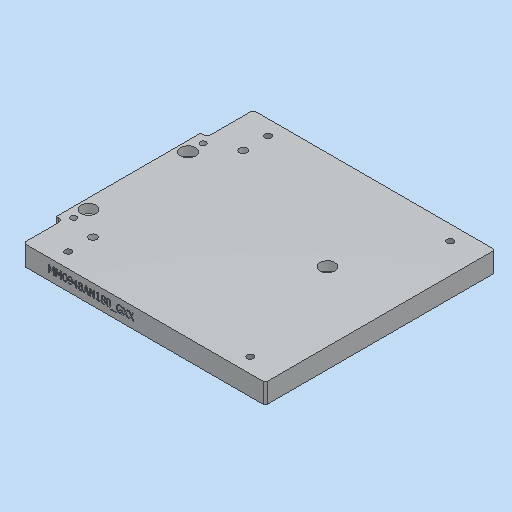
# Autodesk Inventor part: MM0948AN180_G01_106
Saved by Autodesk Inventor 2023.3 (Build 273359000, 359)
## iProperties
Part Number: MM0948AN180_G01_106
Material: 3.3547 AlMg4,5Mn0,7 - AW 5083
Description: =<RBPARTNOTITLE2>
Document SubType Name: Modeling
Designer: ric7an
Mass: 3048.24 g
Surface Area: 1379.15 cm^2
Volume: 1128.98 cm^3
Density: 2.7 g/cm^3
Appearance: Aluminium AnP
Created: 2023-03-23
RBDOCUMENTTYPE: DRF
RBDOCUMENTVERSION: 00
RBDRAWINGMAINSCALE: 1:1
RBDRAWINGMISSINGSPEC: --
RBDRAWINGVOLUME: --
RBGBEDGESIN1: +0,5
RBGBEDGESIN2: +0,2
RBGBEDGESOUT1: -0,3
RBGBEDGESOUT2: -0,1
RBMATERIAL: =<Material>
RBMATMEETS: --
RBMATNO: =<Part Number>
RBPARTMADEOF: 20 x 276 x 249,5 (FM)
RBPARTNO: SIEHE MNR
RBPARTNOTITLE1: manufactured part
RBPARTNOTITLE2: Anfertigungsteil
RBPARTSAFETYINDICATOR: --
RBSURFACE: anodised colourless
RBSURFACE2: eloxiert farblos
RBZEDGESNORM: ISO13715:2002-06
RBZGENDIMCLASS: m
RBZGENDIMNORM: ISO 2768-1:1989-11
RBZGENGEOCLASS: H
RBZGENGEONORM: ISO 2768-2:1989-11
RBZSURFACENORM: ISO13D2:2002-02
RBZTOLERANCENORM: ISO 14405-1:2010-12
AnP_Material: =<Material>
AnP_TemplVers: 20190222
AnP_Kategorie: 1
MaxAbmaße: 20 x 276 x 249,5 (FM)
AnP_Kommentar_aktuell: =<Comments>
AnP_Material_aktuell: =<Material>
Author: FH/Wi
Keywords: =<RBPARTMADEOF>
Comments: =<RBSURFACE2>
Revision Number: 01
Autodesk Inventor part; units mm, degrees
ref_plane "YZ Plane" through (0, 0, 0) normal (1, 0, 0) x (0, 1, 0)
ref_plane "XZ Plane" through (0, 0, 0) normal (0, 1, 0) x (-1, 0, 0)
ref_plane "XY Plane" through (0, 0, 0) normal (0, 0, 1) x (1, 0, 0)
sketch "Skizze1" plane through (0, 0, 0) normal (0, 0, 1) x (1, 0, 0)
  line L0 (-128, 115.5) -> (121.5, 115.5)
  line L1 (121.5, 115.5) -> (121.5, -115.5)
  line L2 (121.5, -115.5) -> (-128, -115.5)
  line L3 (-128, -115.5) -> (-128, 115.5)
  line L4 (0, 161.7) -> (0, -161.7) projected
  line L5 (-177.9, 0) -> (171.4, 0) projected
  point P0 (0, 0)
  dimension "d0" = 249.5
  dimension "d1" = 231
  dimension "d97" = 121.5
  constraints: 8 end point, 2 parallel, 1 horizontal, 1 perpendicular, 1 other
  measures "d0" distance of L0.start L0.end
  measures "d1" distance of L0.end L1.end
  measures "d97" distance between parallel lines of L1 L4
extrude "Extrusion1" add sketch "Skizze1" along normal blind 20
sketch "Skizze3" plane through (0, 0, 20) normal (0, 0, 1) x (1, 0, 0)
  line L0 (-128, 115.5) -> (-128, -115.5) projected
  line L1 (0, 193.2) -> (0, -193.2) projected
  line L2 (-177.9, 0) -> (171.4, 0) projected
  line L3 (121.5, 115.5) -> (-128, 115.5) projected
  point P0 (0, 0)
  point P1 (-118, 61.5)
  point P2 (-118, 46.5)
  point P3 (-118, -53.5)
  point P4 (-118, -68.5)
  point P5 (52, 16.5)
  dimension "d20" = 100
  dimension "d21" = 130
  dimension "d22" = 15
  dimension "d23" = 10
  dimension "d24" = 170
  dimension "d48" = 46.5
  dimension "d52" = 45
  constraints: 3 vertical alignment
  measures "d20" distance of point (-118, -53.5) point (-118, 46.5)
  measures "d21" distance of point (-118, -68.5) point (-118, 61.5)
  measures "d22" distance of point (-118, 46.5) point (-118, 61.5)
  measures "d23" distance from line of point (-118, 61.5) L0
  measures "d24" horizontal distance of point (52, 16.5) point (-118, -53.5)
  measures "d48" distance from line of L2 point (-118, 46.5)
  measures "d52" vertical distance of point (52, 16.5) point (-118, 61.5)
hole "Bohrung3" at (-118, 46.5, 20) at (-118, -53.5, 20) at (52, 16.5, 20) direction (0, 0, -1) diameter 9 end through all counterbore diameter 15 counterbore depth 9 clearance for "Inbusschraube ISO 4762  versenkt" size "M8" standard "ISO"
hole "Bohrung4" at (-118, 61.5, 20) at (-118, -68.5, 20) direction (0, 0, -1) diameter 6 end through all
sketch "Skizze10" plane through (0, 0, 20) normal (0, 0, 1) x (1, 0, 0)
  line L0 (-128, 115.5) -> (-121.5, 115.5)
  line L1 (-121.5, 115.5) -> (-121.5, 69)
  line L2 (-121.5, 69) -> (-128, 69)
  line L3 (-128, 69) -> (-128, 115.5)
  line L4 (121.5, -115.5) -> (121.5, 115.5) projected
  line L5 (-121.5, -76) -> (-128, -76)
  line L6 (-128, -76) -> (-128, -115.5)
  line L7 (-128, -115.5) -> (-121.5, -115.5)
  line L8 (-121.5, -115.5) -> (-121.5, -76)
  circle A0 centre (-118, 46.5) radius 7.5 projected
  circle A1 centre (-118, -53.5) radius 7.5 projected
  line L9 (-118, 46.5) -> (-118, -53.5)
  line L10 (-133.8016, -3.5) -> (-118, -3.5)
  point P0 (0, 0)
  dimension "d84" = 243
  dimension "d85" = 145
  constraints: 20 end point, 4 parallel, 3 horizontal, 2 coincident, 2 perpendicular, 1 collinear, 1 midpoint, 1 vertical, 1 other
  measures "d84" distance between parallel lines of L4 L1
  measures "d85" distance between parallel lines of L5 L2
extrude "Extrusion6" cut sketch "Skizze10" against normal through all contours L0 L1 L2 L3 | L8 L7 L6 L5
chamfer "Fase1" distance 2 angle 45 4 edges at (-121.5, -115.5, 10) (121.5, -115.5, 10) (121.5, 115.5, 10) (-121.5, 115.5, 10)
sketch "Skizze11" plane through (0, 0, 20) normal (0, 0, 1) x (1, 0, 0)
  line L0 (-91.5, 100.5) -> (91.5, 100.5)
  line L1 (91.5, 100.5) -> (91.5, -100.5)
  line L2 (91.5, -100.5) -> (-91.5, -100.5)
  line L3 (-91.5, -100.5) -> (-91.5, 100.5)
  line L4 (121.5, -115.5) -> (121.5, 115.5) projected
  line L5 (121.5, 115.5) -> (-121.5, 115.5) projected
  point P0 (0, 0)
  point P1 (91.5, 0)
  point P2 (121.5, 0)
  point P3 (0, 100.5)
  point P4 (0, 115.5)
  dimension "d95" = 183
  dimension "d96" = 201
  constraints: 8 end point, 4 midpoint, 2 coincident, 2 parallel, 1 horizontal, 1 horizontal alignment, 1 perpendicular, 1 vertical alignment
  measures "d95" distance of L0.start L0.end
  measures "d96" distance of L0.end L1.end
hole "Bohrung7" at (91.5, -100.5, 20) at (-91.5, -100.5, 20) at (-91.5, 100.5, 20) at (91.5, 100.5, 20) direction (0, 0, -1) diameter 6.647 end through all thread size "M8x1.25" designation "M8" class "6H" standard "ISO Metric profile"
fillet "Rundung3" radius 4 2 edges at (-121.5, -76, 10) (-121.5, 69, 10)
sketch "Skizze12" plane through (0, 0, 20) normal (0, 0, 1) x (1, 0, 0)
  circle A0 centre (-91.5, 100.5) radius 3.3235 projected
  circle A1 centre (-91.5, -100.5) radius 3.3235 projected
  line L0 (-91.5, 100.5) -> (-91.5, 75.5)
  line L1 (-91.5, -75.5) -> (-91.5, -100.5)
  point P0 (0, 0)
  dimension "d109" = 25
  dimension "d117" = 25
  constraints: 4 end point, 1 vertical
  measures "d109" distance of L0.start L0.end
  measures "d117" distance of L1.start L1.end
hole "Bohrung8" at (-91.5, -75.5, 20) at (-91.5, 75.5, 20) direction (0, 0, -1) diameter 8 depth 14 tip angle 118
sketch "Skizze13" plane through (0, 0, 20) normal (0, 0, 1) x (1, 0, 0)
  circle A0 centre (-91.5, -75.5) radius 4 projected
  circle A1 centre (-91.5, 75.5) radius 4 projected
  point P0 (0, 0)
  constraints: 2 coincident
hole "Bohrung9" at (-91.5, -75.5, 20) at (-91.5, 75.5, 20) direction (0, 0, -1) diameter 5.5 end through all
sketch "Skizze14" plane through (-119.5, -115.5, 0) normal (0, -1, 0) x (1, 0, 0)
  line L0 (22.2225, 14.2828) -> (108.8886, 14.2828) construction
  line L1 (108.8886, 14.2828) -> (108.8886, 5.7172) construction
  line L2 (108.8886, 5.7172) -> (22.2225, 5.7172) construction
  line L3 (22.2225, 5.7172) -> (22.2225, 14.2828) construction
  line L4 (-8.5, 0) -> (-8.5, 20) projected
  line L5 (28.9332, 7.124) -> (28.0029, 7.124)
  line L6 (28.0029, 7.124) -> (28.0029, 13.154)
  line L7 (28.0029, 13.154) -> (26.1763, 9.0527)
  line L8 (26.1763, 9.0527) -> (25.609, 9.0527)
  line L9 (25.609, 9.0527) -> (23.7995, 13.154)
  line L10 (23.7995, 13.154) -> (23.7995, 7.124)
  line L11 (23.7995, 7.124) -> (22.9316, 7.124)
  line L12 (22.9316, 7.124) -> (22.9316, 14.124)
  line L13 (22.9316, 14.124) -> (24.2022, 14.124)
  line L14 (24.2022, 14.124) -> (25.9494, 10.2269)
  line L15 (25.9494, 10.2269) -> (27.6398, 14.124)
  line L16 (27.6398, 14.124) -> (28.9332, 14.124)
  line L17 (28.9332, 14.124) -> (28.9332, 7.124)
  line L18 (36.3529, 7.124) -> (35.4226, 7.124)
  line L19 (35.4226, 7.124) -> (35.4226, 13.154)
  line L20 (35.4226, 13.154) -> (33.5961, 9.0527)
  line L21 (33.5961, 9.0527) -> (33.0288, 9.0527)
  line L22 (33.0288, 9.0527) -> (31.2192, 13.154)
  line L23 (31.2192, 13.154) -> (31.2192, 7.124)
  line L24 (31.2192, 7.124) -> (30.3513, 7.124)
  line L25 (30.3513, 7.124) -> (30.3513, 14.124)
  line L26 (30.3513, 14.124) -> (31.622, 14.124)
  line L27 (31.622, 14.124) -> (33.3692, 10.2269)
  line L28 (33.3692, 10.2269) -> (35.0596, 14.124)
  line L29 (35.0596, 14.124) -> (36.3529, 14.124)
  line L30 (36.3529, 14.124) -> (36.3529, 7.124)
  spline S0 degree 2 poles (41.9291, 10.624) (41.9291, 8.7407) (40.8343, 6.9765) (39.6941, 6.9765) knots 0 0 0 1 2 2 2
  spline S1 degree 2 poles (39.6941, 6.9765) (38.5369, 6.9765) (37.4534, 8.7747) (37.4534, 10.6183) knots 0 0 0 1 2 2 2
  spline S2 degree 2 poles (37.4534, 10.6183) (37.4534, 12.513) (38.5482, 14.2658) (39.6941, 14.2658) knots 0 0 0 1 2 2 2
  spline S3 degree 2 poles (39.6941, 14.2658) (40.8457, 14.2658) (41.9291, 12.4506) (41.9291, 10.624) knots 0 0 0 1 2 2 2
  spline S4 degree 2 poles (40.7265, 8.4911) (40.8627, 8.8371) (40.9761, 9.9036) (40.9761, 10.624) knots 0 0 0 1 2 2 2
  spline S5 degree 2 poles (40.9761, 10.624) (40.9761, 11.3444) (40.8627, 12.4052) (40.7209, 12.7626) knots 0 0 0 1 2 2 2
  spline S6 degree 2 poles (40.7209, 12.7626) (40.579, 13.1199) (40.0855, 13.4887) (39.6941, 13.4887) knots 0 0 0 1 2 2 2
  spline S7 degree 2 poles (39.6941, 13.4887) (39.3027, 13.4887) (38.7978, 13.1199) (38.6504, 12.7512) knots 0 0 0 1 2 2 2
  spline S8 degree 2 poles (38.6504, 12.7512) (38.5085, 12.3938) (38.4064, 11.3047) (38.4064, 10.6183) knots 0 0 0 1 2 2 2
  spline S9 degree 2 poles (38.4064, 10.6183) (38.4064, 9.8809) (38.4972, 8.8938) (38.6447, 8.5081) knots 0 0 0 1 2 2 2
  spline S10 degree 2 poles (38.6447, 8.5081) (38.7808, 8.1451) (39.2857, 7.7536) (39.6941, 7.7536) knots 0 0 0 1 2 2 2
  spline S11 degree 2 poles (39.6941, 7.7536) (40.0799, 7.7536) (40.5847, 8.1224) (40.7265, 8.4911) knots 0 0 0 1 2 2 2
  spline S12 degree 2 poles (42.6325, 11.8493) (42.6325, 12.3882) (42.9842, 13.2844) (43.2905, 13.6078) knots 0 0 0 1 2 2 2
  spline S13 degree 2 poles (43.2905, 13.6078) (43.5799, 13.9198) (44.4251, 14.2658) (44.8562, 14.2658) knots 0 0 0 1 2 2 2
  spline S14 degree 2 poles (44.8562, 14.2658) (45.3384, 14.2658) (46.1212, 13.9425) (46.4105, 13.6361) knots 0 0 0 1 2 2 2
  spline S15 degree 2 poles (46.4105, 13.6361) (46.7735, 13.2504) (47.1706, 12.0024) (47.1706, 11.0438) knots 0 0 0 1 2 2 2
  spline S16 degree 2 poles (47.1706, 11.0438) (47.1706, 10.1759) (46.7792, 8.6216) (46.3991, 8.1053) knots 0 0 0 1 2 2 2
  spline S17 degree 2 poles (46.3991, 8.1053) (45.9964, 7.5608) (44.8619, 6.9878) (44.0337, 6.9878) knots 0 0 0 1 2 2 2
  spline S18 degree 2 poles (44.0337, 6.9878) (43.8465, 6.9878) (43.421, 7.0276) (43.2395, 7.0843) knots 0 0 0 1 2 2 2
  line L31 (43.2395, 7.0843) -> (43.2395, 7.9862)
  line L32 (43.2395, 7.9862) -> (43.2849, 7.9862)
  spline S19 degree 2 poles (43.2849, 7.9862) (43.404, 7.9182) (43.9032, 7.799) (44.1585, 7.799) knots 0 0 0 1 2 2 2
  spline S20 degree 2 poles (44.1585, 7.799) (45.0774, 7.799) (46.1269, 9.013) (46.2006, 10.1361) knots 0 0 0 1 2 2 2
  spline S21 degree 2 poles (46.2006, 10.1361) (45.8262, 9.8809) (45.1455, 9.6483) (44.7427, 9.6483) knots 0 0 0 1 2 2 2
  spline S22 degree 2 poles (44.7427, 9.6483) (44.357, 9.6483) (43.716, 9.8185) (43.3927, 10.0624) knots 0 0 0 1 2 2 2
  spline S23 degree 2 poles (43.3927, 10.0624) (43.0183, 10.3517) (42.6325, 11.231) (42.6325, 11.8493) knots 0 0 0 1 2 2 2
  spline S24 degree 2 poles (46.2233, 11.2536) (46.2233, 11.9627) (45.9623, 12.859) (45.7298, 13.1029) knots 0 0 0 1 2 2 2
  spline S25 degree 2 poles (45.7298, 13.1029) (45.5256, 13.3298) (45.1001, 13.5) (44.8505, 13.5) knots 0 0 0 1 2 2 2
  spline S26 degree 2 poles (44.8505, 13.5) (44.2719, 13.5) (43.5855, 12.6718) (43.5855, 11.889) knots 0 0 0 1 2 2 2
  spline S27 degree 2 poles (43.5855, 11.889) (43.5855, 11.4465) (43.8124, 10.8736) (44.062, 10.6694) knots 0 0 0 1 2 2 2
  spline S28 degree 2 poles (44.062, 10.6694) (44.2435, 10.5219) (44.6917, 10.4254) (44.9526, 10.4254) knots 0 0 0 1 2 2 2
  spline S29 degree 2 poles (44.9526, 10.4254) (45.2533, 10.4254) (45.9453, 10.6353) (46.2063, 10.8112) knots 0 0 0 1 2 2 2
  spline S30 degree 2 poles (46.2063, 10.8112) (46.2119, 10.8793) (46.2233, 11.1118) (46.2233, 11.2536) knots 0 0 0 1 2 2 2
  line L33 (52.5823, 9.5292) -> (51.7484, 9.5292)
  line L34 (51.7484, 9.5292) -> (51.7484, 7.124)
  line L35 (51.7484, 7.124) -> (50.8465, 7.124)
  line L36 (50.8465, 7.124) -> (50.8465, 9.5292)
  line L37 (50.8465, 9.5292) -> (47.7549, 9.5292)
  line L38 (47.7549, 9.5292) -> (47.7549, 10.5162)
  line L39 (47.7549, 10.5162) -> (50.8862, 14.124)
  line L40 (50.8862, 14.124) -> (51.7484, 14.124)
  line L41 (51.7484, 14.124) -> (51.7484, 10.2836)
  line L42 (51.7484, 10.2836) -> (52.5823, 10.2836)
  line L43 (52.5823, 10.2836) -> (52.5823, 9.5292)
  line L44 (50.8465, 10.2836) -> (50.8465, 13.0178)
  line L45 (50.8465, 13.0178) -> (48.4923, 10.2836)
  line L46 (48.4923, 10.2836) -> (50.8465, 10.2836)
  spline S31 degree 2 poles (55.4469, 6.9652) (54.9251, 6.9652) (54.0685, 7.2771) (53.7679, 7.5665) knots 0 0 0 1 2 2 2
  spline S32 degree 2 poles (53.7679, 7.5665) (53.4729, 7.8501) (53.1666, 8.6216) (53.1666, 9.0583) knots 0 0 0 1 2 2 2
  spline S33 degree 2 poles (53.1666, 9.0583) (53.1666, 9.6256) (53.7735, 10.5786) (54.3521, 10.8622) knots 0 0 0 1 2 2 2
  line L47 (54.3521, 10.8622) -> (54.3521, 10.8906)
  spline S34 degree 2 poles (54.3521, 10.8906) (53.8359, 11.1912) (53.3367, 11.906) (53.3367, 12.4392) knots 0 0 0 1 2 2 2
  spline S35 degree 2 poles (53.3367, 12.4392) (53.3367, 13.2277) (54.528, 14.2828) (55.4469, 14.2828) knots 0 0 0 1 2 2 2
  spline S36 degree 2 poles (55.4469, 14.2828) (56.3999, 14.2828) (57.5515, 13.2844) (57.5515, 12.5016) knots 0 0 0 1 2 2 2
  spline S37 degree 2 poles (57.5515, 12.5016) (57.5515, 12.0308) (57.0012, 11.1118) (56.485, 10.8509) knots 0 0 0 1 2 2 2
  line L48 (56.485, 10.8509) -> (56.485, 10.8225)
  spline S38 degree 2 poles (56.485, 10.8225) (57.0977, 10.5389) (57.7273, 9.722) (57.7273, 9.0754) knots 0 0 0 1 2 2 2
  spline S39 degree 2 poles (57.7273, 9.0754) (57.7273, 8.1791) (56.4226, 6.9652) (55.4469, 6.9652) knots 0 0 0 1 2 2 2
  spline S40 degree 2 poles (56.763, 8.9846) (56.763, 9.4157) (56.4226, 9.9263) (55.9405, 10.1872) knots 0 0 0 1 2 2 2
  spline S41 degree 2 poles (55.9405, 10.1872) (55.7816, 10.278) (55.2484, 10.4878) (54.9137, 10.624) knots 0 0 0 1 2 2 2
  spline S42 degree 2 poles (54.9137, 10.624) (54.528, 10.3687) (54.1139, 9.6086) (54.1139, 9.1264) knots 0 0 0 1 2 2 2
  spline S43 degree 2 poles (54.1139, 9.1264) (54.1139, 8.4911) (54.8797, 7.6629) (55.4583, 7.6629) knots 0 0 0 1 2 2 2
  spline S44 degree 2 poles (55.4583, 7.6629) (56.0482, 7.6629) (56.763, 8.372) (56.763, 8.9846) knots 0 0 0 1 2 2 2
  spline S45 degree 2 poles (56.6325, 12.4903) (56.6325, 12.9611) (56.0029, 13.5908) (55.4413, 13.5908) knots 0 0 0 1 2 2 2
  spline S46 degree 2 poles (55.4413, 13.5908) (54.9307, 13.5908) (54.2784, 13.0292) (54.2784, 12.547) knots 0 0 0 1 2 2 2
  spline S47 degree 2 poles (54.2784, 12.547) (54.2784, 12.201) (54.6131, 11.7188) (54.9478, 11.5259) knots 0 0 0 1 2 2 2
  spline S48 degree 2 poles (54.9478, 11.5259) (55.0896, 11.4465) (55.6909, 11.1686) (55.9348, 11.0891) knots 0 0 0 1 2 2 2
  spline S49 degree 2 poles (55.9348, 11.0891) (56.3432, 11.4011) (56.6325, 12.0648) (56.6325, 12.4903) knots 0 0 0 1 2 2 2
  line L49 (58.028, 7.124) -> (60.3878, 14.124)
  line L50 (60.3878, 14.124) -> (61.5337, 14.124)
  line L51 (61.5337, 14.124) -> (63.8935, 7.124)
  line L52 (63.8935, 7.124) -> (62.9121, 7.124)
  line L53 (62.9121, 7.124) -> (62.2768, 9.081)
  line L54 (62.2768, 9.081) -> (59.605, 9.081)
  line L55 (59.605, 9.081) -> (58.9696, 7.124)
  line L56 (58.9696, 7.124) -> (58.028, 7.124)
  line L57 (62.0215, 9.8752) -> (60.938, 13.171)
  line L58 (60.938, 13.171) -> (59.8602, 9.8752)
  line L59 (59.8602, 9.8752) -> (62.0215, 9.8752)
  line L60 (69.5661, 7.124) -> (68.5223, 7.124)
  line L61 (68.5223, 7.124) -> (65.4251, 13.1596)
  line L62 (65.4251, 13.1596) -> (65.4251, 7.124)
  line L63 (65.4251, 7.124) -> (64.5572, 7.124)
  line L64 (64.5572, 7.124) -> (64.5572, 14.124)
  line L65 (64.5572, 14.124) -> (65.8789, 14.124)
  line L66 (65.8789, 14.124) -> (68.6982, 8.5818)
  line L67 (68.6982, 8.5818) -> (68.6982, 14.124)
  line L68 (68.6982, 14.124) -> (69.5661, 14.124)
  line L69 (69.5661, 14.124) -> (69.5661, 7.124)
  line L70 (74.7508, 7.124) -> (71.3359, 7.124)
  line L71 (71.3359, 7.124) -> (71.3359, 7.8387)
  line L72 (71.3359, 7.8387) -> (72.6066, 7.8387)
  line L73 (72.6066, 7.8387) -> (72.6066, 12.53)
  line L74 (72.6066, 12.53) -> (71.3359, 12.53)
  line L75 (71.3359, 12.53) -> (71.3359, 13.171)
  spline S50 degree 2 poles (71.3359, 13.171) (72.0563, 13.171) (72.7371, 13.5794) (72.7824, 14.1467) knots 0 0 0 1 2 2 2
  line L76 (72.7824, 14.1467) -> (73.5085, 14.1467)
  line L77 (73.5085, 14.1467) -> (73.5085, 7.8387)
  line L78 (73.5085, 7.8387) -> (74.7508, 7.8387)
  line L79 (74.7508, 7.8387) -> (74.7508, 7.124)
  spline S51 degree 2 poles (78.1544, 6.9652) (77.6325, 6.9652) (76.776, 7.2771) (76.4753, 7.5665) knots 0 0 0 1 2 2 2
  spline S52 degree 2 poles (76.4753, 7.5665) (76.1803, 7.8501) (75.874, 8.6216) (75.874, 9.0583) knots 0 0 0 1 2 2 2
  spline S53 degree 2 poles (75.874, 9.0583) (75.874, 9.6256) (76.481, 10.5786) (77.0596, 10.8622) knots 0 0 0 1 2 2 2
  line L80 (77.0596, 10.8622) -> (77.0596, 10.8906)
  spline S54 degree 2 poles (77.0596, 10.8906) (76.5434, 11.1912) (76.0442, 11.906) (76.0442, 12.4392) knots 0 0 0 1 2 2 2
  spline S55 degree 2 poles (76.0442, 12.4392) (76.0442, 13.2277) (77.2354, 14.2828) (78.1544, 14.2828) knots 0 0 0 1 2 2 2
  spline S56 degree 2 poles (78.1544, 14.2828) (79.1074, 14.2828) (80.2589, 13.2844) (80.2589, 12.5016) knots 0 0 0 1 2 2 2
  spline S57 degree 2 poles (80.2589, 12.5016) (80.2589, 12.0308) (79.7087, 11.1118) (79.1925, 10.8509) knots 0 0 0 1 2 2 2
  line L81 (79.1925, 10.8509) -> (79.1925, 10.8225)
  spline S58 degree 2 poles (79.1925, 10.8225) (79.8051, 10.5389) (80.4348, 9.722) (80.4348, 9.0754) knots 0 0 0 1 2 2 2
  spline S59 degree 2 poles (80.4348, 9.0754) (80.4348, 8.1791) (79.1301, 6.9652) (78.1544, 6.9652) knots 0 0 0 1 2 2 2
  spline S60 degree 2 poles (79.4704, 8.9846) (79.4704, 9.4157) (79.1301, 9.9263) (78.6479, 10.1872) knots 0 0 0 1 2 2 2
  spline S61 degree 2 poles (78.6479, 10.1872) (78.4891, 10.278) (77.9559, 10.4878) (77.6212, 10.624) knots 0 0 0 1 2 2 2
  spline S62 degree 2 poles (77.6212, 10.624) (77.2354, 10.3687) (76.8213, 9.6086) (76.8213, 9.1264) knots 0 0 0 1 2 2 2
  spline S63 degree 2 poles (76.8213, 9.1264) (76.8213, 8.4911) (77.5871, 7.6629) (78.1657, 7.6629) knots 0 0 0 1 2 2 2
  spline S64 degree 2 poles (78.1657, 7.6629) (78.7557, 7.6629) (79.4704, 8.372) (79.4704, 8.9846) knots 0 0 0 1 2 2 2
  spline S65 degree 2 poles (79.34, 12.4903) (79.34, 12.9611) (78.7103, 13.5908) (78.1487, 13.5908) knots 0 0 0 1 2 2 2
  spline S66 degree 2 poles (78.1487, 13.5908) (77.6382, 13.5908) (76.9858, 13.0292) (76.9858, 12.547) knots 0 0 0 1 2 2 2
  spline S67 degree 2 poles (76.9858, 12.547) (76.9858, 12.201) (77.3205, 11.7188) (77.6552, 11.5259) knots 0 0 0 1 2 2 2
  spline S68 degree 2 poles (77.6552, 11.5259) (77.797, 11.4465) (78.3983, 11.1686) (78.6422, 11.0891) knots 0 0 0 1 2 2 2
  spline S69 degree 2 poles (78.6422, 11.0891) (79.0507, 11.4011) (79.34, 12.0648) (79.34, 12.4903) knots 0 0 0 1 2 2 2
  spline S70 degree 2 poles (85.6479, 10.624) (85.6479, 8.7407) (84.5531, 6.9765) (83.4129, 6.9765) knots 0 0 0 1 2 2 2
  spline S71 degree 2 poles (83.4129, 6.9765) (82.2557, 6.9765) (81.1722, 8.7747) (81.1722, 10.6183) knots 0 0 0 1 2 2 2
  spline S72 degree 2 poles (81.1722, 10.6183) (81.1722, 12.513) (82.267, 14.2658) (83.4129, 14.2658) knots 0 0 0 1 2 2 2
  spline S73 degree 2 poles (83.4129, 14.2658) (84.5645, 14.2658) (85.6479, 12.4506) (85.6479, 10.624) knots 0 0 0 1 2 2 2
  spline S74 degree 2 poles (84.4453, 8.4911) (84.5815, 8.8371) (84.6949, 9.9036) (84.6949, 10.624) knots 0 0 0 1 2 2 2
  spline S75 degree 2 poles (84.6949, 10.624) (84.6949, 11.3444) (84.5815, 12.4052) (84.4397, 12.7626) knots 0 0 0 1 2 2 2
  spline S76 degree 2 poles (84.4397, 12.7626) (84.2978, 13.1199) (83.8043, 13.4887) (83.4129, 13.4887) knots 0 0 0 1 2 2 2
  spline S77 degree 2 poles (83.4129, 13.4887) (83.0215, 13.4887) (82.5166, 13.1199) (82.3692, 12.7512) knots 0 0 0 1 2 2 2
  spline S78 degree 2 poles (82.3692, 12.7512) (82.2273, 12.3938) (82.1252, 11.3047) (82.1252, 10.6183) knots 0 0 0 1 2 2 2
  spline S79 degree 2 poles (82.1252, 10.6183) (82.1252, 9.8809) (82.216, 8.8938) (82.3635, 8.5081) knots 0 0 0 1 2 2 2
  spline S80 degree 2 poles (82.3635, 8.5081) (82.4996, 8.1451) (83.0045, 7.7536) (83.4129, 7.7536) knots 0 0 0 1 2 2 2
  spline S81 degree 2 poles (83.4129, 7.7536) (83.7987, 7.7536) (84.3035, 8.1224) (84.4453, 8.4911) knots 0 0 0 1 2 2 2
  line L82 (91.3602, 5.7172) -> (85.9599, 5.7172)
  line L83 (85.9599, 5.7172) -> (85.9599, 6.3241)
  line L84 (85.9599, 6.3241) -> (91.3602, 6.3241)
  line L85 (91.3602, 6.3241) -> (91.3602, 5.7172)
  spline S82 degree 2 poles (94.9283, 6.9878) (94.1852, 6.9878) (92.9542, 7.4417) (92.5118, 7.9011) knots 0 0 0 1 2 2 2
  spline S83 degree 2 poles (92.5118, 7.9011) (92.0693, 8.3663) (91.5985, 9.7391) (91.5985, 10.6297) knots 0 0 0 1 2 2 2
  spline S84 degree 2 poles (91.5985, 10.6297) (91.5985, 11.4749) (92.075, 12.8136) (92.5175, 13.2901) knots 0 0 0 1 2 2 2
  spline S85 degree 2 poles (92.5175, 13.2901) (92.9429, 13.7496) (94.1909, 14.2488) (94.934, 14.2488) knots 0 0 0 1 2 2 2
  spline S86 degree 2 poles (94.934, 14.2488) (95.2914, 14.2488) (95.938, 14.1467) (96.233, 14.0559) knots 0 0 0 1 2 2 2
  spline S87 degree 2 poles (96.233, 14.0559) (96.4713, 13.9878) (97.0499, 13.7382) (97.2257, 13.6475) knots 0 0 0 1 2 2 2
  line L86 (97.2257, 13.6475) -> (97.2257, 12.5243)
  line L87 (97.2257, 12.5243) -> (97.1463, 12.5243)
  spline S88 degree 2 poles (97.1463, 12.5243) (96.9704, 12.6775) (96.6017, 12.9554) (96.2614, 13.1143) knots 0 0 0 1 2 2 2
  spline S89 degree 2 poles (96.2614, 13.1143) (95.9777, 13.2561) (95.246, 13.4433) (94.8262, 13.4433) knots 0 0 0 1 2 2 2
  spline S90 degree 2 poles (94.8262, 13.4433) (93.8165, 13.4433) (92.5685, 11.923) (92.5685, 10.658) knots 0 0 0 1 2 2 2
  spline S91 degree 2 poles (92.5685, 10.658) (92.5685, 9.9546) (92.8975, 8.8995) (93.2095, 8.5365) knots 0 0 0 1 2 2 2
  spline S92 degree 2 poles (93.2095, 8.5365) (93.5102, 8.1734) (94.361, 7.7934) (94.8943, 7.7934) knots 0 0 0 1 2 2 2
  spline S93 degree 2 poles (94.8943, 7.7934) (95.2857, 7.7934) (96.0685, 7.9068) (96.3351, 8.0203) knots 0 0 0 1 2 2 2
  line L88 (96.3351, 8.0203) -> (96.3351, 9.8298)
  line L89 (96.3351, 9.8298) -> (94.7128, 9.8298)
  line L90 (94.7128, 9.8298) -> (94.7128, 10.6467)
  line L91 (94.7128, 10.6467) -> (97.2541, 10.6467)
  line L92 (97.2541, 10.6467) -> (97.2541, 7.5891)
  spline S94 degree 2 poles (97.2541, 7.5891) (97.0782, 7.5097) (96.4769, 7.2658) (96.2217, 7.1921) knots 0 0 0 1 2 2 2
  spline S95 degree 2 poles (96.2217, 7.1921) (95.8756, 7.09) (95.3197, 6.9878) (94.9283, 6.9878) knots 0 0 0 1 2 2 2
  line L93 (103.2614, 7.124) -> (102.1949, 7.124)
  line L94 (102.1949, 7.124) -> (100.4931, 9.9149)
  line L95 (100.4931, 9.9149) -> (98.7573, 7.124)
  line L96 (98.7573, 7.124) -> (97.7533, 7.124)
  line L97 (97.7533, 7.124) -> (99.9826, 10.6297)
  line L98 (99.9826, 10.6297) -> (97.8213, 14.124)
  line L99 (97.8213, 14.124) -> (98.8878, 14.124)
  line L100 (98.8878, 14.124) -> (100.5555, 11.3841)
  line L101 (100.5555, 11.3841) -> (102.2573, 14.124)
  line L102 (102.2573, 14.124) -> (103.2614, 14.124)
  line L103 (103.2614, 14.124) -> (101.0717, 10.675)
  line L104 (101.0717, 10.675) -> (103.2614, 7.124)
  line L105 (108.8489, 7.124) -> (107.7824, 7.124)
  line L106 (107.7824, 7.124) -> (106.0807, 9.9149)
  line L107 (106.0807, 9.9149) -> (104.3448, 7.124)
  line L108 (104.3448, 7.124) -> (103.3408, 7.124)
  line L109 (103.3408, 7.124) -> (105.5701, 10.6297)
  line L110 (105.5701, 10.6297) -> (103.4089, 14.124)
  line L111 (103.4089, 14.124) -> (104.4753, 14.124)
  line L112 (104.4753, 14.124) -> (106.1431, 11.3841)
  line L113 (106.1431, 11.3841) -> (107.8448, 14.124)
  line L114 (107.8448, 14.124) -> (108.8489, 14.124)
  line L115 (108.8489, 14.124) -> (106.6593, 10.675)
  line L116 (106.6593, 10.675) -> (108.8489, 7.124)
  point P0 (119.5, 0)
  point P1 (-8.5, 10)
  point P2 (22.2225, 10)
  constraints: 2 midpoint, 1 horizontal alignment, 2 other
emboss "Prägen1" sketch "Skizze14" operation cut depth 0.1 direction (0, 1, 0)
equation "\"d22\" = -0.5 * d20 + 0.5 * d21"
